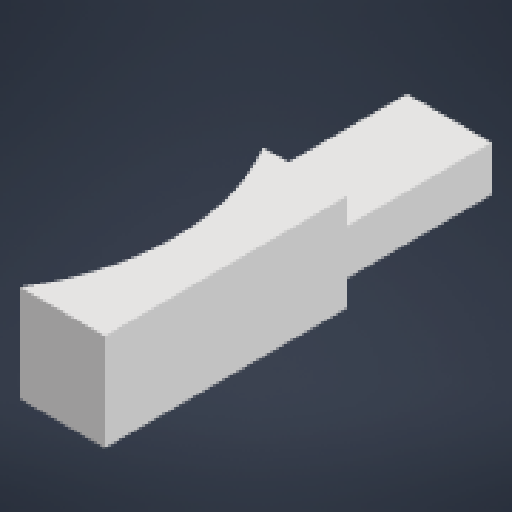
# Autodesk Inventor part: pinza
Saved by Autodesk Inventor 2027.1 (Build 311270010, 270A)
## iProperties
Created: 2026-11-02
Part Number: pinza
Material: Genérico
Document SubType Name: Modeling
Designer: MANGEL
Density: 1 g/cm^3
Appearance: Valor por defecto
Author: MANGEL
Autodesk Inventor part; units mm, degrees
ref_plane "YZ Plane" through (0, 0, 0) normal (1, 0, 0) x (0, 1, 0)
ref_plane "XZ Plane" through (0, 0, 0) normal (0, 1, 0) x (-1, 0, 0)
ref_plane "XY Plane" through (0, 0, 0) normal (0, 0, 1) x (1, 0, 0)
sketch "Boceto7" plane through (0, 0, 0) normal (1, 0, 0) x (0, 1, 0)
  line L0 (-10.05, 40.05) -> (10.05, 40.05)
  line L1 (10.05, 40.05) -> (10.05, -40.05)
  line L2 (10.05, -40.05) -> (-10.05, -40.05)
  line L3 (-10.05, -40.05) -> (-10.05, 40.05)
  line L4 (-10.05, 40.05) -> (10.05, -40.05) construction
  line L5 (10.05, 40.05) -> (-10.05, -40.05) construction
  point P0 (0, 0)
  dimension "d16" = 80.1
  dimension "d17" = 20.1
  constraints: 12 end point, 2 midpoint, 2 parallel, 1 horizontal, 1 perpendicular
  measures "d16" distance of L0.end L1.end
  measures "d17" distance of L1.end L2.end
extrude "Extrusión7" add sketch "Boceto7" along normal blind 17.5
sketch "Boceto9" plane through (17.5, 0, 0) normal (1, 0, 0) x (0, 0, -1)
  line L0 (40.05, 4.7) -> (10.15, 4.7)
  line L1 (10.15, 4.7) -> (10.15, -4.7)
  line L2 (10.15, -4.7) -> (40.05, -4.7)
  line L3 (40.05, -4.7) -> (40.05, 4.7)
  line L4 (-40.05, 10.05) -> (-40.05, -10.05) projected
  line L5 (40.05, -10.05) -> (40.05, 10.05) projected
  line L6 (40.05, 10.05) -> (-40.05, 10.05) projected
  line L7 (10.15, 10.05) -> (40.05, 10.05)
  line L8 (40.05, 10.05) -> (40.05, 4.7)
  line L9 (40.05, 4.7) -> (10.15, 4.7)
  line L10 (10.15, 4.7) -> (10.15, 10.05)
  line L11 (-40.05, -10.05) -> (40.05, -10.05) projected
  line L12 (10.15, -4.7) -> (40.05, -4.7)
  line L13 (40.05, -4.7) -> (40.05, -10.05)
  line L14 (40.05, -10.05) -> (10.15, -10.05)
  line L15 (10.15, -10.05) -> (10.15, -4.7)
  point P0 (0, 0)
  point P1 (10.15, 0)
  point P2 (-40.05, 0)
  point P3 (10.15, -10.05)
  point P4 (10.15, 4.7)
  dimension "d21" = 50.2
  dimension "d22" = 9.4
  constraints: 24 end point, 6 parallel, 3 horizontal, 3 perpendicular, 2 collinear, 2 midpoint, 1 horizontal alignment, 1 point on line
  measures "d21" distance between parallel lines of L4 L1
  measures "d22" distance of L0.end L1.end
extrude "Extrusión8" cut sketch "Boceto9" against normal blind 17.5 contours L0 L10 L6 L5 | L5 L11 L15 L2
sketch "Boceto10" plane through (0, 10.05, 40.05) normal (0, 1, 0) x (1, 0, 0)
  line L0 (0, 0) -> (17.5, 0) projected
  line L1 (0, 50.2) -> (0, 80.1) projected
  arc A0 (0, 0) -> (0, 50.2) centre (-41.2429, 25.1) ccw
  line L2 (0, 50.2) -> (0, 0) projected
  line L3 (0, 0) -> (0, 50.2)
  point P0 (0, 40.05)
  constraints: 2 end point, 2 point on circle, 1 centre point, 1 vertical
extrude "Extrusión9" cut sketch "Boceto10" against normal through all
sketch "Boceto11" plane through (17.5, 4.7, -10.15) normal (0, 1, 0) x (1, 0, 0)
  circle A0 centre (-12.55, 24.95) radius 2.25
  line L0 (-17.5, 29.9) -> (0, 29.9) projected
  line L1 (-17.5, 0) -> (-17.5, 29.9) projected
  point P0 (-17.5, -10.15)
  dimension "d27" = 4.5
  dimension "d28" = 4.95
  dimension "d29" = 4.95
  constraints: 1 centre point
  measures "d27" diameter of A0
  measures "d28" distance from line of L0 A0.centre
  measures "d29" distance from line of L1 A0.centre
extrude "Extrusión10" cut sketch "Boceto11" against normal through all
